Autodesk Fusion 360 part; units mm, degrees
(part 3 of 7)
sketch "T nut envelope sketch (3)" plane through (0, 0, 17) normal (0, 0, 1) x (1, 0, 0) in component "REFERENCE M5 slot-6 T nut 02"
  line L0 (7.2, 223) -> (16.8, 223)
  line L1 (16.8, 223) -> (16.8, 233)
  line L2 (16.8, 233) -> (7.2, 233)
  line L3 (7.2, 233) -> (7.2, 223)
  dimension "d912" = 7.2
  dimension "d913" = 223
  dimension "d914" = 9.6
  dimension "d915" = 10
  constraint horizontal L0
  constraint vertical L1
  constraint horizontal L2
  constraint vertical L3
  measures "d912" horizontal distance of origin L0.start
  measures "d913" vertical distance of origin L0.start
  measures "d914" horizontal distance of L0.start L0.end
  measures "d915" vertical distance of L0.end L1.end
extrude "T nut envelope''" add sketch "T nut envelope sketch (3)" along normal blind 4 separate body makes body 30 in component "REFERENCE M5 slot-6 T nut 02"
ref_plane "WorkPlane2" through (0, 0, 17) normal (0, 0, 1) x (1, 0, 0) in component "REFERENCE M5 slot-6 T nut 02"
sketch "Thread envelope sketch (3)" plane through (0, 0, 17) normal (0, 0, 1) x (1, 0, 0) in component "REFERENCE M5 slot-6 T nut 02"
  circle A0 centre (12, 228) radius 2.6
  dimension "d920" = 12
  dimension "d921" = 228
  dimension "d922" = 5.2
  measures "d920" horizontal distance of origin A0.centre
  measures "d921" vertical distance of origin A0.centre
  measures "d922" diameter of A0
extrude "Thread envelope''" cut sketch "Thread envelope sketch (3)" along normal blind 4 bodies 29 in component "REFERENCE M5 screw 02 - length follows stack"
extrude "Extrude2''" cut sketch "Thread envelope sketch (3)" along normal blind 4 bodies 30 in component "REFERENCE M5 slot-6 T nut 02"
ref_plane "WorkPlane1" through (0, 0, -2) normal (0, 0, 1) x (1, 0, 0) in component "METAL cap 10"
sketch "Visible cap sketch (4)" plane through (0, 0, -2) normal (0, 0, 1) x (1, 0, 0) in component "METAL cap 10"
  circle A0 centre (120, 12) radius 9
  dimension "d929" = 120
  dimension "d930" = 12
  dimension "d931" = 18
  measures "d929" horizontal distance of origin A0.centre
  measures "d930" vertical distance of origin A0.centre
  measures "d931" diameter of A0
extrude "Visible cap'''" add sketch "Visible cap sketch (4)" along normal blind 2 separate body makes body 31 in component "METAL cap 10"
ref_plane "WorkPlane2" through (0, 0, -2) normal (0, 0, 1) x (1, 0, 0) in component "METAL cap 10"
sketch "M5 clearance sketch (4)" plane through (0, 0, -2) normal (0, 0, 1) x (1, 0, 0) in component "METAL cap 10"
  circle A0 centre (120, 12) radius 2.75
  dimension "d936" = 120
  dimension "d937" = 12
  dimension "d938" = 5.5
  measures "d936" horizontal distance of origin A0.centre
  measures "d937" vertical distance of origin A0.centre
  measures "d938" diameter of A0
extrude "M5 clearance'''" cut sketch "M5 clearance sketch (4)" along normal blind 2 bodies 31 in component "METAL cap 10"
ref_plane "WorkPlane1" through (0, 0, 5) normal (0, 0, 1) x (1, 0, 0) in component "PRINT rear bearing seat 10"
sketch "Rear bearing seat sketch (4)" plane through (0, 0, 5) normal (0, 0, 1) x (1, 0, 0) in component "PRINT rear bearing seat 10"
  circle A0 centre (120, 12) radius 9
  dimension "d943" = 120
  dimension "d944" = 12
  dimension "d945" = 18
  measures "d943" horizontal distance of origin A0.centre
  measures "d944" vertical distance of origin A0.centre
  measures "d945" diameter of A0
extrude "Rear bearing seat'''" add sketch "Rear bearing seat sketch (4)" along normal blind 2 separate body makes body 32 in component "PRINT rear bearing seat 10"
ref_plane "WorkPlane2" through (0, 0, 5) normal (0, 0, 1) x (1, 0, 0) in component "PRINT rear bearing seat 10"
sketch "Shoulder clearance sketch (4)" plane through (0, 0, 5) normal (0, 0, 1) x (1, 0, 0) in component "PRINT rear bearing seat 10"
  circle A0 centre (120, 12) radius 4.2
  dimension "d950" = 120
  dimension "d951" = 12
  dimension "d952" = 8.4
  measures "d950" horizontal distance of origin A0.centre
  measures "d951" vertical distance of origin A0.centre
  measures "d952" diameter of A0
extrude "Shoulder clearance'''" cut sketch "Shoulder clearance sketch (4)" along normal blind 2 bodies 32 in component "PRINT rear bearing seat 10"
sketch "8 mm shoulder sketch (4)" plane through (0, 0, 0) normal (0, 0, 1) x (1, 0, 0) in component "METAL stepped compression spacer 10"
  circle A0 centre (120, 12) radius 4
  dimension "d955" = 120
  dimension "d956" = 12
  dimension "d957" = 8
  measures "d955" horizontal distance of origin A0.centre
  measures "d956" vertical distance of origin A0.centre
  measures "d957" diameter of A0
extrude "8 mm shoulder'''" add sketch "8 mm shoulder sketch (4)" along normal blind 7 separate body makes body 33 in component "METAL stepped compression spacer 10"
ref_plane "WorkPlane1" through (0, 0, 7) normal (0, 0, 1) x (1, 0, 0) in component "METAL stepped compression spacer 10"
sketch "12 mm base sketch (4)" plane through (0, 0, 7) normal (0, 0, 1) x (1, 0, 0) in component "METAL stepped compression spacer 10"
  circle A0 centre (120, 12) radius 6
  dimension "d962" = 120
  dimension "d963" = 12
  dimension "d964" = 12
  measures "d962" horizontal distance of origin A0.centre
  measures "d963" vertical distance of origin A0.centre
  measures "d964" diameter of A0
extrude "12 mm base'''" add sketch "12 mm base sketch (4)" along normal blind 8 bodies 33 in component "METAL stepped compression spacer 10"
sketch "Through bore sketch (4)" plane through (0, 0, 0) normal (0, 0, 1) x (1, 0, 0) in component "METAL stepped compression spacer 10"
  circle A0 centre (120, 12) radius 2.75
  dimension "d967" = 120
  dimension "d968" = 12
  dimension "d969" = 5.5
  measures "d967" horizontal distance of origin A0.centre
  measures "d968" vertical distance of origin A0.centre
  measures "d969" diameter of A0
extrude "Through bore'''" cut sketch "Through bore sketch (4)" along normal blind 15 bodies 33 in component "METAL stepped compression spacer 10"
ref_plane "WorkPlane1" through (0, 0, -5) normal (0, 0, 1) x (1, 0, 0) in component "REFERENCE M5 screw 10 - length follows stack"
sketch "Nominal button head sketch (4)" plane through (0, 0, -5) normal (0, 0, 1) x (1, 0, 0) in component "REFERENCE M5 screw 10 - length follows stack"
  circle A0 centre (120, 12) radius 4.75
  dimension "d974" = 120
  dimension "d975" = 12
  dimension "d976" = 9.5
  measures "d974" horizontal distance of origin A0.centre
  measures "d975" vertical distance of origin A0.centre
  measures "d976" diameter of A0
extrude "Nominal button head'''" add sketch "Nominal button head sketch (4)" along normal blind 3 separate body makes body 34 in component "REFERENCE M5 screw 10 - length follows stack"
ref_plane "WorkPlane2" through (0, 0, -2) normal (0, 0, 1) x (1, 0, 0) in component "REFERENCE M5 screw 10 - length follows stack"
sketch "Unthreaded shank envelope sketch (4)" plane through (0, 0, -2) normal (0, 0, 1) x (1, 0, 0) in component "REFERENCE M5 screw 10 - length follows stack"
  circle A0 centre (120, 12) radius 2.5
  dimension "d981" = 120
  dimension "d982" = 12
  dimension "d983" = 5
  measures "d981" horizontal distance of origin A0.centre
  measures "d982" vertical distance of origin A0.centre
  measures "d983" diameter of A0
extrude "Unthreaded shank envelope'''" add sketch "Unthreaded shank envelope sketch (4)" along normal blind 22 bodies 34 in component "REFERENCE M5 screw 10 - length follows stack"
ref_plane "WorkPlane1" through (0, 0, 17) normal (0, 0, 1) x (1, 0, 0) in component "REFERENCE M5 slot-6 T nut 10"
sketch "T nut envelope sketch (4)" plane through (0, 0, 17) normal (0, 0, 1) x (1, 0, 0) in component "REFERENCE M5 slot-6 T nut 10"
  line L0 (115.2, 7) -> (124.8, 7)
  line L1 (124.8, 7) -> (124.8, 17)
  line L2 (124.8, 17) -> (115.2, 17)
  line L3 (115.2, 17) -> (115.2, 7)
  dimension "d988" = 115.2
  dimension "d989" = 7
  dimension "d990" = 9.6
  dimension "d991" = 10
  constraint horizontal L0
  constraint vertical L1
  constraint horizontal L2
  constraint vertical L3
  measures "d988" horizontal distance of origin L0.start
  measures "d989" vertical distance of origin L0.start
  measures "d990" horizontal distance of L0.start L0.end
  measures "d991" vertical distance of L0.end L1.end
extrude "T nut envelope'''" add sketch "T nut envelope sketch (4)" along normal blind 4 separate body makes body 35 in component "REFERENCE M5 slot-6 T nut 10"
ref_plane "WorkPlane2" through (0, 0, 17) normal (0, 0, 1) x (1, 0, 0) in component "REFERENCE M5 slot-6 T nut 10"
sketch "Thread envelope sketch (4)" plane through (0, 0, 17) normal (0, 0, 1) x (1, 0, 0) in component "REFERENCE M5 slot-6 T nut 10"
  circle A0 centre (120, 12) radius 2.6
  dimension "d996" = 120
  dimension "d997" = 12
  dimension "d998" = 5.2
  measures "d996" horizontal distance of origin A0.centre
  measures "d997" vertical distance of origin A0.centre
  measures "d998" diameter of A0
extrude "Thread envelope'''" cut sketch "Thread envelope sketch (4)" along normal blind 4 bodies 34 in component "REFERENCE M5 screw 10 - length follows stack"
extrude "Extrude2'''" cut sketch "Thread envelope sketch (4)" along normal blind 4 bodies 35 in component "REFERENCE M5 slot-6 T nut 10"
ref_plane "WorkPlane1" through (0, 0, -2) normal (0, 0, 1) x (1, 0, 0) in component "METAL cap 11"
sketch "Visible cap sketch (5)" plane through (0, 0, -2) normal (0, 0, 1) x (1, 0, 0) in component "METAL cap 11"
  circle A0 centre (120, 120) radius 9
  dimension "d1005" = 120
  dimension "d1006" = 120
  dimension "d1007" = 18
  measures "d1005" horizontal distance of origin A0.centre
  measures "d1006" vertical distance of origin A0.centre
  measures "d1007" diameter of A0
extrude "Visible cap''''" add sketch "Visible cap sketch (5)" along normal blind 2 separate body makes body 36 in component "METAL cap 11"
ref_plane "WorkPlane2" through (0, 0, -2) normal (0, 0, 1) x (1, 0, 0) in component "METAL cap 11"
sketch "M5 clearance sketch (5)" plane through (0, 0, -2) normal (0, 0, 1) x (1, 0, 0) in component "METAL cap 11"
  circle A0 centre (120, 120) radius 2.75
  dimension "d1012" = 120
  dimension "d1013" = 120
  dimension "d1014" = 5.5
  measures "d1012" horizontal distance of origin A0.centre
  measures "d1013" vertical distance of origin A0.centre
  measures "d1014" diameter of A0
extrude "M5 clearance''''" cut sketch "M5 clearance sketch (5)" along normal blind 2 bodies 36 in component "METAL cap 11"
ref_plane "WorkPlane1" through (0, 0, 5) normal (0, 0, 1) x (1, 0, 0) in component "PRINT rear bearing seat 11"
sketch "Rear bearing seat sketch (5)" plane through (0, 0, 5) normal (0, 0, 1) x (1, 0, 0) in component "PRINT rear bearing seat 11"
  circle A0 centre (120, 120) radius 9
  dimension "d1019" = 120
  dimension "d1020" = 120
  dimension "d1021" = 18
  measures "d1019" horizontal distance of origin A0.centre
  measures "d1020" vertical distance of origin A0.centre
  measures "d1021" diameter of A0
extrude "Rear bearing seat''''" add sketch "Rear bearing seat sketch (5)" along normal blind 2 separate body makes body 37 in component "PRINT rear bearing seat 11"
ref_plane "WorkPlane2" through (0, 0, 5) normal (0, 0, 1) x (1, 0, 0) in component "PRINT rear bearing seat 11"
sketch "Shoulder clearance sketch (5)" plane through (0, 0, 5) normal (0, 0, 1) x (1, 0, 0) in component "PRINT rear bearing seat 11"
  circle A0 centre (120, 120) radius 4.2
  dimension "d1026" = 120
  dimension "d1027" = 120
  dimension "d1028" = 8.4
  measures "d1026" horizontal distance of origin A0.centre
  measures "d1027" vertical distance of origin A0.centre
  measures "d1028" diameter of A0
extrude "Shoulder clearance''''" cut sketch "Shoulder clearance sketch (5)" along normal blind 2 bodies 37 in component "PRINT rear bearing seat 11"
sketch "8 mm shoulder sketch (5)" plane through (0, 0, 0) normal (0, 0, 1) x (1, 0, 0) in component "METAL stepped compression spacer 11"
  circle A0 centre (120, 120) radius 4
  dimension "d1031" = 120
  dimension "d1032" = 120
  dimension "d1033" = 8
  measures "d1031" horizontal distance of origin A0.centre
  measures "d1032" vertical distance of origin A0.centre
  measures "d1033" diameter of A0
extrude "8 mm shoulder''''" add sketch "8 mm shoulder sketch (5)" along normal blind 7 separate body makes body 38 in component "METAL stepped compression spacer 11"
ref_plane "WorkPlane1" through (0, 0, 7) normal (0, 0, 1) x (1, 0, 0) in component "METAL stepped compression spacer 11"
sketch "12 mm base sketch (5)" plane through (0, 0, 7) normal (0, 0, 1) x (1, 0, 0) in component "METAL stepped compression spacer 11"
  circle A0 centre (120, 120) radius 6
  dimension "d1038" = 120
  dimension "d1039" = 120
  dimension "d1040" = 12
  measures "d1038" horizontal distance of origin A0.centre
  measures "d1039" vertical distance of origin A0.centre
  measures "d1040" diameter of A0
extrude "12 mm base''''" add sketch "12 mm base sketch (5)" along normal blind 8 bodies 38 in component "METAL stepped compression spacer 11"
sketch "Through bore sketch (5)" plane through (0, 0, 0) normal (0, 0, 1) x (1, 0, 0) in component "METAL stepped compression spacer 11"
  circle A0 centre (120, 120) radius 2.75
  dimension "d1043" = 120
  dimension "d1044" = 120
  dimension "d1045" = 5.5
  measures "d1043" horizontal distance of origin A0.centre
  measures "d1044" vertical distance of origin A0.centre
  measures "d1045" diameter of A0
extrude "Through bore''''" cut sketch "Through bore sketch (5)" along normal blind 15 bodies 38 in component "METAL stepped compression spacer 11"
ref_plane "WorkPlane1" through (0, 0, -5) normal (0, 0, 1) x (1, 0, 0) in component "REFERENCE M5 screw 11 - length follows stack"
sketch "Nominal button head sketch (5)" plane through (0, 0, -5) normal (0, 0, 1) x (1, 0, 0) in component "REFERENCE M5 screw 11 - length follows stack"
  circle A0 centre (120, 120) radius 4.75
  dimension "d1050" = 120
  dimension "d1051" = 120
  dimension "d1052" = 9.5
  measures "d1050" horizontal distance of origin A0.centre
  measures "d1051" vertical distance of origin A0.centre
  measures "d1052" diameter of A0
extrude "Nominal button head''''" add sketch "Nominal button head sketch (5)" along normal blind 3 separate body makes body 39 in component "REFERENCE M5 screw 11 - length follows stack"
ref_plane "WorkPlane2" through (0, 0, -2) normal (0, 0, 1) x (1, 0, 0) in component "REFERENCE M5 screw 11 - length follows stack"
sketch "Unthreaded shank envelope sketch (5)" plane through (0, 0, -2) normal (0, 0, 1) x (1, 0, 0) in component "REFERENCE M5 screw 11 - length follows stack"
  circle A0 centre (120, 120) radius 2.5
  dimension "d1057" = 120
  dimension "d1058" = 120
  dimension "d1059" = 5
  measures "d1057" horizontal distance of origin A0.centre
  measures "d1058" vertical distance of origin A0.centre
  measures "d1059" diameter of A0
extrude "Unthreaded shank envelope''''" add sketch "Unthreaded shank envelope sketch (5)" along normal blind 22 bodies 39 in component "REFERENCE M5 screw 11 - length follows stack"
ref_plane "WorkPlane1" through (0, 0, 17) normal (0, 0, 1) x (1, 0, 0) in component "REFERENCE M5 slot-6 T nut 11"
sketch "T nut envelope sketch (5)" plane through (0, 0, 17) normal (0, 0, 1) x (1, 0, 0) in component "REFERENCE M5 slot-6 T nut 11"
  line L0 (115.2, 115) -> (124.8, 115)
  line L1 (124.8, 115) -> (124.8, 125)
  line L2 (124.8, 125) -> (115.2, 125)
  line L3 (115.2, 125) -> (115.2, 115)
  dimension "d1064" = 115.2
  dimension "d1065" = 115
  dimension "d1066" = 9.6
  dimension "d1067" = 10
  constraint horizontal L0
  constraint vertical L1
  constraint horizontal L2
  constraint vertical L3
  measures "d1064" horizontal distance of origin L0.start
  measures "d1065" vertical distance of origin L0.start
  measures "d1066" horizontal distance of L0.start L0.end
  measures "d1067" vertical distance of L0.end L1.end
extrude "T nut envelope''''" add sketch "T nut envelope sketch (5)" along normal blind 4 separate body makes body 40 in component "REFERENCE M5 slot-6 T nut 11"
ref_plane "WorkPlane2" through (0, 0, 17) normal (0, 0, 1) x (1, 0, 0) in component "REFERENCE M5 slot-6 T nut 11"
sketch "Thread envelope sketch (5)" plane through (0, 0, 17) normal (0, 0, 1) x (1, 0, 0) in component "REFERENCE M5 slot-6 T nut 11"
  circle A0 centre (120, 120) radius 2.6
  dimension "d1072" = 120
  dimension "d1073" = 120
  dimension "d1074" = 5.2
  measures "d1072" horizontal distance of origin A0.centre
  measures "d1073" vertical distance of origin A0.centre
  measures "d1074" diameter of A0
extrude "Thread envelope''''" cut sketch "Thread envelope sketch (5)" along normal blind 4 bodies 39 in component "REFERENCE M5 screw 11 - length follows stack"
extrude "Extrude2''''" cut sketch "Thread envelope sketch (5)" along normal blind 4 bodies 40 in component "REFERENCE M5 slot-6 T nut 11"
ref_plane "WorkPlane1" through (0, 0, -2) normal (0, 0, 1) x (1, 0, 0) in component "METAL cap 12"
sketch "Visible cap sketch (6)" plane through (0, 0, -2) normal (0, 0, 1) x (1, 0, 0) in component "METAL cap 12"
  circle A0 centre (120, 228) radius 9
  dimension "d1081" = 120
  dimension "d1082" = 228
  dimension "d1083" = 18
  measures "d1081" horizontal distance of origin A0.centre
  measures "d1082" vertical distance of origin A0.centre
  measures "d1083" diameter of A0
extrude "Visible cap'''''" add sketch "Visible cap sketch (6)" along normal blind 2 separate body makes body 41 in component "METAL cap 12"
ref_plane "WorkPlane2" through (0, 0, -2) normal (0, 0, 1) x (1, 0, 0) in component "METAL cap 12"
sketch "M5 clearance sketch (6)" plane through (0, 0, -2) normal (0, 0, 1) x (1, 0, 0) in component "METAL cap 12"
  circle A0 centre (120, 228) radius 2.75
  dimension "d1088" = 120
  dimension "d1089" = 228
  dimension "d1090" = 5.5
  measures "d1088" horizontal distance of origin A0.centre
  measures "d1089" vertical distance of origin A0.centre
  measures "d1090" diameter of A0
extrude "M5 clearance'''''" cut sketch "M5 clearance sketch (6)" along normal blind 2 bodies 41 in component "METAL cap 12"
ref_plane "WorkPlane1" through (0, 0, 5) normal (0, 0, 1) x (1, 0, 0) in component "PRINT rear bearing seat 12"
sketch "Rear bearing seat sketch (6)" plane through (0, 0, 5) normal (0, 0, 1) x (1, 0, 0) in component "PRINT rear bearing seat 12"
  circle A0 centre (120, 228) radius 9
  dimension "d1095" = 120
  dimension "d1096" = 228
  dimension "d1097" = 18
  measures "d1095" horizontal distance of origin A0.centre
  measures "d1096" vertical distance of origin A0.centre
  measures "d1097" diameter of A0
extrude "Rear bearing seat'''''" add sketch "Rear bearing seat sketch (6)" along normal blind 2 separate body makes body 42 in component "PRINT rear bearing seat 12"
ref_plane "WorkPlane2" through (0, 0, 5) normal (0, 0, 1) x (1, 0, 0) in component "PRINT rear bearing seat 12"
sketch "Shoulder clearance sketch (6)" plane through (0, 0, 5) normal (0, 0, 1) x (1, 0, 0) in component "PRINT rear bearing seat 12"
  circle A0 centre (120, 228) radius 4.2
  dimension "d1102" = 120
  dimension "d1103" = 228
  dimension "d1104" = 8.4
  measures "d1102" horizontal distance of origin A0.centre
  measures "d1103" vertical distance of origin A0.centre
  measures "d1104" diameter of A0
extrude "Shoulder clearance'''''" cut sketch "Shoulder clearance sketch (6)" along normal blind 2 bodies 42 in component "PRINT rear bearing seat 12"
sketch "8 mm shoulder sketch (6)" plane through (0, 0, 0) normal (0, 0, 1) x (1, 0, 0) in component "METAL stepped compression spacer 12"
  circle A0 centre (120, 228) radius 4
  dimension "d1107" = 120
  dimension "d1108" = 228
  dimension "d1109" = 8
  measures "d1107" horizontal distance of origin A0.centre
  measures "d1108" vertical distance of origin A0.centre
  measures "d1109" diameter of A0
extrude "8 mm shoulder'''''" add sketch "8 mm shoulder sketch (6)" along normal blind 7 separate body makes body 43 in component "METAL stepped compression spacer 12"
ref_plane "WorkPlane1" through (0, 0, 7) normal (0, 0, 1) x (1, 0, 0) in component "METAL stepped compression spacer 12"
sketch "12 mm base sketch (6)" plane through (0, 0, 7) normal (0, 0, 1) x (1, 0, 0) in component "METAL stepped compression spacer 12"
  circle A0 centre (120, 228) radius 6
  dimension "d1114" = 120
  dimension "d1115" = 228
  dimension "d1116" = 12
  measures "d1114" horizontal distance of origin A0.centre
  measures "d1115" vertical distance of origin A0.centre
  measures "d1116" diameter of A0
extrude "12 mm base'''''" add sketch "12 mm base sketch (6)" along normal blind 8 bodies 43 in component "METAL stepped compression spacer 12"
sketch "Through bore sketch (6)" plane through (0, 0, 0) normal (0, 0, 1) x (1, 0, 0) in component "METAL stepped compression spacer 12"
  circle A0 centre (120, 228) radius 2.75
  dimension "d1119" = 120
  dimension "d1120" = 228
  dimension "d1121" = 5.5
  measures "d1119" horizontal distance of origin A0.centre
  measures "d1120" vertical distance of origin A0.centre
  measures "d1121" diameter of A0
extrude "Through bore'''''" cut sketch "Through bore sketch (6)" along normal blind 15 bodies 43 in component "METAL stepped compression spacer 12"
ref_plane "WorkPlane1" through (0, 0, -5) normal (0, 0, 1) x (1, 0, 0) in component "REFERENCE M5 screw 12 - length follows stack"
sketch "Nominal button head sketch (6)" plane through (0, 0, -5) normal (0, 0, 1) x (1, 0, 0) in component "REFERENCE M5 screw 12 - length follows stack"
  circle A0 centre (120, 228) radius 4.75
  dimension "d1126" = 120
  dimension "d1127" = 228
  dimension "d1128" = 9.5
  measures "d1126" horizontal distance of origin A0.centre
  measures "d1127" vertical distance of origin A0.centre
  measures "d1128" diameter of A0
extrude "Nominal button head'''''" add sketch "Nominal button head sketch (6)" along normal blind 3 separate body makes body 44 in component "REFERENCE M5 screw 12 - length follows stack"
ref_plane "WorkPlane2" through (0, 0, -2) normal (0, 0, 1) x (1, 0, 0) in component "REFERENCE M5 screw 12 - length follows stack"
sketch "Unthreaded shank envelope sketch (6)" plane through (0, 0, -2) normal (0, 0, 1) x (1, 0, 0) in component "REFERENCE M5 screw 12 - length follows stack"
  circle A0 centre (120, 228) radius 2.5
  dimension "d1133" = 120
  dimension "d1134" = 228
  dimension "d1135" = 5
  measures "d1133" horizontal distance of origin A0.centre
  measures "d1134" vertical distance of origin A0.centre
  measures "d1135" diameter of A0
extrude "Unthreaded shank envelope'''''" add sketch "Unthreaded shank envelope sketch (6)" along normal blind 22 bodies 44 in component "REFERENCE M5 screw 12 - length follows stack"
ref_plane "WorkPlane1" through (0, 0, 17) normal (0, 0, 1) x (1, 0, 0) in component "REFERENCE M5 slot-6 T nut 12"
sketch "T nut envelope sketch (6)" plane through (0, 0, 17) normal (0, 0, 1) x (1, 0, 0) in component "REFERENCE M5 slot-6 T nut 12"
  line L0 (115.2, 223) -> (124.8, 223)
  line L1 (124.8, 223) -> (124.8, 233)
  line L2 (124.8, 233) -> (115.2, 233)
  line L3 (115.2, 233) -> (115.2, 223)
  dimension "d1140" = 115.2
  dimension "d1141" = 223
  dimension "d1142" = 9.6
  dimension "d1143" = 10
  constraint horizontal L0
  constraint vertical L1
  constraint horizontal L2
  constraint vertical L3
  measures "d1140" horizontal distance of origin L0.start
  measures "d1141" vertical distance of origin L0.start
  measures "d1142" horizontal distance of L0.start L0.end
  measures "d1143" vertical distance of L0.end L1.end
extrude "T nut envelope'''''" add sketch "T nut envelope sketch (6)" along normal blind 4 separate body makes body 45 in component "REFERENCE M5 slot-6 T nut 12"
ref_plane "WorkPlane2" through (0, 0, 17) normal (0, 0, 1) x (1, 0, 0) in component "REFERENCE M5 slot-6 T nut 12"
sketch "Thread envelope sketch (6)" plane through (0, 0, 17) normal (0, 0, 1) x (1, 0, 0) in component "REFERENCE M5 slot-6 T nut 12"
  circle A0 centre (120, 228) radius 2.6
  dimension "d1148" = 120
  dimension "d1149" = 228
  dimension "d1150" = 5.2
  measures "d1148" horizontal distance of origin A0.centre
  measures "d1149" vertical distance of origin A0.centre
  measures "d1150" diameter of A0
extrude "Thread envelope'''''" cut sketch "Thread envelope sketch (6)" along normal blind 4 bodies 44 in component "REFERENCE M5 screw 12 - length follows stack"
extrude "Extrude2'''''" cut sketch "Thread envelope sketch (6)" along normal blind 4 bodies 45 in component "REFERENCE M5 slot-6 T nut 12"
ref_plane "WorkPlane1" through (0, 0, -2) normal (0, 0, 1) x (1, 0, 0) in component "METAL cap 20"
sketch "Visible cap sketch (7)" plane through (0, 0, -2) normal (0, 0, 1) x (1, 0, 0) in component "METAL cap 20"
  circle A0 centre (228, 12) radius 9
  dimension "d1157" = 228
  dimension "d1158" = 12
  dimension "d1159" = 18
  measures "d1157" horizontal distance of origin A0.centre
  measures "d1158" vertical distance of origin A0.centre
  measures "d1159" diameter of A0
extrude "Visible cap''''''" add sketch "Visible cap sketch (7)" along normal blind 2 separate body makes body 46 in component "METAL cap 20"
ref_plane "WorkPlane2" through (0, 0, -2) normal (0, 0, 1) x (1, 0, 0) in component "METAL cap 20"
sketch "M5 clearance sketch (7)" plane through (0, 0, -2) normal (0, 0, 1) x (1, 0, 0) in component "METAL cap 20"
  circle A0 centre (228, 12) radius 2.75
  dimension "d1164" = 228
  dimension "d1165" = 12
  dimension "d1166" = 5.5
  measures "d1164" horizontal distance of origin A0.centre
  measures "d1165" vertical distance of origin A0.centre
  measures "d1166" diameter of A0
extrude "M5 clearance''''''" cut sketch "M5 clearance sketch (7)" along normal blind 2 bodies 46 in component "METAL cap 20"
ref_plane "WorkPlane1" through (0, 0, 5) normal (0, 0, 1) x (1, 0, 0) in component "PRINT rear bearing seat 20"
sketch "Rear bearing seat sketch (7)" plane through (0, 0, 5) normal (0, 0, 1) x (1, 0, 0) in component "PRINT rear bearing seat 20"
  circle A0 centre (228, 12) radius 9
  dimension "d1171" = 228
  dimension "d1172" = 12
  dimension "d1173" = 18
  measures "d1171" horizontal distance of origin A0.centre
  measures "d1172" vertical distance of origin A0.centre
  measures "d1173" diameter of A0
extrude "Rear bearing seat''''''" add sketch "Rear bearing seat sketch (7)" along normal blind 2 separate body makes body 47 in component "PRINT rear bearing seat 20"
ref_plane "WorkPlane2" through (0, 0, 5) normal (0, 0, 1) x (1, 0, 0) in component "PRINT rear bearing seat 20"
sketch "Shoulder clearance sketch (7)" plane through (0, 0, 5) normal (0, 0, 1) x (1, 0, 0) in component "PRINT rear bearing seat 20"
  circle A0 centre (228, 12) radius 4.2
  dimension "d1178" = 228
  dimension "d1179" = 12
  dimension "d1180" = 8.4
  measures "d1178" horizontal distance of origin A0.centre
  measures "d1179" vertical distance of origin A0.centre
  measures "d1180" diameter of A0
extrude "Shoulder clearance''''''" cut sketch "Shoulder clearance sketch (7)" along normal blind 2 bodies 47 in component "PRINT rear bearing seat 20"
sketch "8 mm shoulder sketch (7)" plane through (0, 0, 0) normal (0, 0, 1) x (1, 0, 0) in component "METAL stepped compression spacer 20"
  circle A0 centre (228, 12) radius 4
  dimension "d1183" = 228
  dimension "d1184" = 12
  dimension "d1185" = 8
  measures "d1183" horizontal distance of origin A0.centre
  measures "d1184" vertical distance of origin A0.centre
  measures "d1185" diameter of A0
extrude "8 mm shoulder''''''" add sketch "8 mm shoulder sketch (7)" along normal blind 7 separate body makes body 48 in component "METAL stepped compression spacer 20"
ref_plane "WorkPlane1" through (0, 0, 7) normal (0, 0, 1) x (1, 0, 0) in component "METAL stepped compression spacer 20"
sketch "12 mm base sketch (7)" plane through (0, 0, 7) normal (0, 0, 1) x (1, 0, 0) in component "METAL stepped compression spacer 20"
  circle A0 centre (228, 12) radius 6
  dimension "d1190" = 228
  dimension "d1191" = 12
  dimension "d1192" = 12
  measures "d1190" horizontal distance of origin A0.centre
  measures "d1191" vertical distance of origin A0.centre
  measures "d1192" diameter of A0
extrude "12 mm base''''''" add sketch "12 mm base sketch (7)" along normal blind 8 bodies 48 in component "METAL stepped compression spacer 20"
sketch "Through bore sketch (7)" plane through (0, 0, 0) normal (0, 0, 1) x (1, 0, 0) in component "METAL stepped compression spacer 20"
  circle A0 centre (228, 12) radius 2.75
  dimension "d1195" = 228
  dimension "d1196" = 12
  dimension "d1197" = 5.5
  measures "d1195" horizontal distance of origin A0.centre
  measures "d1196" vertical distance of origin A0.centre
  measures "d1197" diameter of A0
extrude "Through bore''''''" cut sketch "Through bore sketch (7)" along normal blind 15 bodies 48 in component "METAL stepped compression spacer 20"
ref_plane "WorkPlane1" through (0, 0, -5) normal (0, 0, 1) x (1, 0, 0) in component "REFERENCE M5 screw 20 - length follows stack"
sketch "Nominal button head sketch (7)" plane through (0, 0, -5) normal (0, 0, 1) x (1, 0, 0) in component "REFERENCE M5 screw 20 - length follows stack"
  circle A0 centre (228, 12) radius 4.75
  dimension "d1202" = 228
  dimension "d1203" = 12
  dimension "d1204" = 9.5
  measures "d1202" horizontal distance of origin A0.centre
  measures "d1203" vertical distance of origin A0.centre
  measures "d1204" diameter of A0
extrude "Nominal button head''''''" add sketch "Nominal button head sketch (7)" along normal blind 3 separate body makes body 49 in component "REFERENCE M5 screw 20 - length follows stack"
ref_plane "WorkPlane2" through (0, 0, -2) normal (0, 0, 1) x (1, 0, 0) in component "REFERENCE M5 screw 20 - length follows stack"
sketch "Unthreaded shank envelope sketch (7)" plane through (0, 0, -2) normal (0, 0, 1) x (1, 0, 0) in component "REFERENCE M5 screw 20 - length follows stack"
  circle A0 centre (228, 12) radius 2.5
  dimension "d1209" = 228
  dimension "d1210" = 12
  dimension "d1211" = 5
  measures "d1209" horizontal distance of origin A0.centre
  measures "d1210" vertical distance of origin A0.centre
  measures "d1211" diameter of A0
extrude "Unthreaded shank envelope''''''" add sketch "Unthreaded shank envelope sketch (7)" along normal blind 22 bodies 49 in component "REFERENCE M5 screw 20 - length follows stack"
ref_plane "WorkPlane1" through (0, 0, 17) normal (0, 0, 1) x (1, 0, 0) in component "REFERENCE M5 slot-6 T nut 20"
sketch "T nut envelope sketch (7)" plane through (0, 0, 17) normal (0, 0, 1) x (1, 0, 0) in component "REFERENCE M5 slot-6 T nut 20"
  line L0 (223.2, 7) -> (232.8, 7)
  line L1 (232.8, 7) -> (232.8, 17)
  line L2 (232.8, 17) -> (223.2, 17)
  line L3 (223.2, 17) -> (223.2, 7)
  dimension "d1216" = 223.2
  dimension "d1217" = 7
  dimension "d1218" = 9.6
  dimension "d1219" = 10
  constraint horizontal L0
  constraint vertical L1
  constraint horizontal L2
  constraint vertical L3
  measures "d1216" horizontal distance of origin L0.start
  measures "d1217" vertical distance of origin L0.start
  measures "d1218" horizontal distance of L0.start L0.end
  measures "d1219" vertical distance of L0.end L1.end
extrude "T nut envelope''''''" add sketch "T nut envelope sketch (7)" along normal blind 4 separate body makes body 50 in component "REFERENCE M5 slot-6 T nut 20"
ref_plane "WorkPlane2" through (0, 0, 17) normal (0, 0, 1) x (1, 0, 0) in component "REFERENCE M5 slot-6 T nut 20"
sketch "Thread envelope sketch (7)" plane through (0, 0, 17) normal (0, 0, 1) x (1, 0, 0) in component "REFERENCE M5 slot-6 T nut 20"
  circle A0 centre (228, 12) radius 2.6
  dimension "d1224" = 228
  dimension "d1225" = 12
  dimension "d1226" = 5.2
  measures "d1224" horizontal distance of origin A0.centre
  measures "d1225" vertical distance of origin A0.centre
  measures "d1226" diameter of A0
extrude "Thread envelope''''''" cut sketch "Thread envelope sketch (7)" along normal blind 4 bodies 49 in component "REFERENCE M5 screw 20 - length follows stack"
extrude "Extrude2''''''" cut sketch "Thread envelope sketch (7)" along normal blind 4 bodies 50 in component "REFERENCE M5 slot-6 T nut 20"
ref_plane "WorkPlane1" through (0, 0, -2) normal (0, 0, 1) x (1, 0, 0) in component "METAL cap 21"
sketch "Visible cap sketch (8)" plane through (0, 0, -2) normal (0, 0, 1) x (1, 0, 0) in component "METAL cap 21"
  circle A0 centre (228, 120) radius 9
  dimension "d1233" = 228
  dimension "d1234" = 120
  dimension "d1235" = 18
  measures "d1233" horizontal distance of origin A0.centre
  measures "d1234" vertical distance of origin A0.centre
  measures "d1235" diameter of A0
extrude "Visible cap'''''''" add sketch "Visible cap sketch (8)" along normal blind 2 separate body makes body 51 in component "METAL cap 21"
ref_plane "WorkPlane2" through (0, 0, -2) normal (0, 0, 1) x (1, 0, 0) in component "METAL cap 21"
sketch "M5 clearance sketch (8)" plane through (0, 0, -2) normal (0, 0, 1) x (1, 0, 0) in component "METAL cap 21"
  circle A0 centre (228, 120) radius 2.75
  dimension "d1240" = 228
  dimension "d1241" = 120
  dimension "d1242" = 5.5
  measures "d1240" horizontal distance of origin A0.centre
  measures "d1241" vertical distance of origin A0.centre
  measures "d1242" diameter of A0
extrude "M5 clearance'''''''" cut sketch "M5 clearance sketch (8)" along normal blind 2 bodies 51 in component "METAL cap 21"
ref_plane "WorkPlane1" through (0, 0, 5) normal (0, 0, 1) x (1, 0, 0) in component "PRINT rear bearing seat 21"
sketch "Rear bearing seat sketch (8)" plane through (0, 0, 5) normal (0, 0, 1) x (1, 0, 0) in component "PRINT rear bearing seat 21"
  circle A0 centre (228, 120) radius 9
  dimension "d1247" = 228
  dimension "d1248" = 120
  dimension "d1249" = 18
  measures "d1247" horizontal distance of origin A0.centre
  measures "d1248" vertical distance of origin A0.centre
  measures "d1249" diameter of A0
extrude "Rear bearing seat'''''''" add sketch "Rear bearing seat sketch (8)" along normal blind 2 separate body makes body 52 in component "PRINT rear bearing seat 21"
ref_plane "WorkPlane2" through (0, 0, 5) normal (0, 0, 1) x (1, 0, 0) in component "PRINT rear bearing seat 21"
sketch "Shoulder clearance sketch (8)" plane through (0, 0, 5) normal (0, 0, 1) x (1, 0, 0) in component "PRINT rear bearing seat 21"
  circle A0 centre (228, 120) radius 4.2
  dimension "d1254" = 228
  dimension "d1255" = 120
  dimension "d1256" = 8.4
  measures "d1254" horizontal distance of origin A0.centre
  measures "d1255" vertical distance of origin A0.centre
  measures "d1256" diameter of A0
extrude "Shoulder clearance'''''''" cut sketch "Shoulder clearance sketch (8)" along normal blind 2 bodies 52 in component "PRINT rear bearing seat 21"
sketch "8 mm shoulder sketch (8)" plane through (0, 0, 0) normal (0, 0, 1) x (1, 0, 0) in component "METAL stepped compression spacer 21"
  circle A0 centre (228, 120) radius 4
  dimension "d1259" = 228
  dimension "d1260" = 120
  dimension "d1261" = 8
  measures "d1259" horizontal distance of origin A0.centre
  measures "d1260" vertical distance of origin A0.centre
  measures "d1261" diameter of A0
extrude "8 mm shoulder'''''''" add sketch "8 mm shoulder sketch (8)" along normal blind 7 separate body makes body 53 in component "METAL stepped compression spacer 21"
ref_plane "WorkPlane1" through (0, 0, 7) normal (0, 0, 1) x (1, 0, 0) in component "METAL stepped compression spacer 21"
sketch "12 mm base sketch (8)" plane through (0, 0, 7) normal (0, 0, 1) x (1, 0, 0) in component "METAL stepped compression spacer 21"
  circle A0 centre (228, 120) radius 6
  dimension "d1266" = 228
  dimension "d1267" = 120
  dimension "d1268" = 12
  measures "d1266" horizontal distance of origin A0.centre
  measures "d1267" vertical distance of origin A0.centre
  measures "d1268" diameter of A0
extrude "12 mm base'''''''" add sketch "12 mm base sketch (8)" along normal blind 8 bodies 53 in component "METAL stepped compression spacer 21"
sketch "Through bore sketch (8)" plane through (0, 0, 0) normal (0, 0, 1) x (1, 0, 0) in component "METAL stepped compression spacer 21"
  circle A0 centre (228, 120) radius 2.75
  dimension "d1271" = 228
  dimension "d1272" = 120
  dimension "d1273" = 5.5
  measures "d1271" horizontal distance of origin A0.centre
  measures "d1272" vertical distance of origin A0.centre
  measures "d1273" diameter of A0
extrude "Through bore'''''''" cut sketch "Through bore sketch (8)" along normal blind 15 bodies 53 in component "METAL stepped compression spacer 21"
ref_plane "WorkPlane1" through (0, 0, -5) normal (0, 0, 1) x (1, 0, 0) in component "REFERENCE M5 screw 21 - length follows stack"
sketch "Nominal button head sketch (8)" plane through (0, 0, -5) normal (0, 0, 1) x (1, 0, 0) in component "REFERENCE M5 screw 21 - length follows stack"
  circle A0 centre (228, 120) radius 4.75
  dimension "d1278" = 228
  dimension "d1279" = 120
  dimension "d1280" = 9.5
  measures "d1278" horizontal distance of origin A0.centre
  measures "d1279" vertical distance of origin A0.centre
  measures "d1280" diameter of A0
extrude "Nominal button head'''''''" add sketch "Nominal button head sketch (8)" along normal blind 3 separate body makes body 54 in component "REFERENCE M5 screw 21 - length follows stack"
ref_plane "WorkPlane2" through (0, 0, -2) normal (0, 0, 1) x (1, 0, 0) in component "REFERENCE M5 screw 21 - length follows stack"
sketch "Unthreaded shank envelope sketch (8)" plane through (0, 0, -2) normal (0, 0, 1) x (1, 0, 0) in component "REFERENCE M5 screw 21 - length follows stack"
  circle A0 centre (228, 120) radius 2.5
  dimension "d1285" = 228
  dimension "d1286" = 120
  dimension "d1287" = 5
  measures "d1285" horizontal distance of origin A0.centre
  measures "d1286" vertical distance of origin A0.centre
  measures "d1287" diameter of A0
extrude "Unthreaded shank envelope'''''''" add sketch "Unthreaded shank envelope sketch (8)" along normal blind 22 bodies 54 in component "REFERENCE M5 screw 21 - length follows stack"
ref_plane "WorkPlane1" through (0, 0, 17) normal (0, 0, 1) x (1, 0, 0) in component "REFERENCE M5 slot-6 T nut 21"
sketch "T nut envelope sketch (8)" plane through (0, 0, 17) normal (0, 0, 1) x (1, 0, 0) in component "REFERENCE M5 slot-6 T nut 21"
  line L0 (223.2, 115) -> (232.8, 115)
  line L1 (232.8, 115) -> (232.8, 125)
  line L2 (232.8, 125) -> (223.2, 125)
  line L3 (223.2, 125) -> (223.2, 115)
  dimension "d1292" = 223.2
  dimension "d1293" = 115
  dimension "d1294" = 9.6
  dimension "d1295" = 10
  constraint horizontal L0
  constraint vertical L1
  constraint horizontal L2
  constraint vertical L3
  measures "d1292" horizontal distance of origin L0.start
  measures "d1293" vertical distance of origin L0.start
  measures "d1294" horizontal distance of L0.start L0.end
  measures "d1295" vertical distance of L0.end L1.end
extrude "T nut envelope'''''''" add sketch "T nut envelope sketch (8)" along normal blind 4 separate body makes body 55 in component "REFERENCE M5 slot-6 T nut 21"
ref_plane "WorkPlane2" through (0, 0, 17) normal (0, 0, 1) x (1, 0, 0) in component "REFERENCE M5 slot-6 T nut 21"
sketch "Thread envelope sketch (8)" plane through (0, 0, 17) normal (0, 0, 1) x (1, 0, 0) in component "REFERENCE M5 slot-6 T nut 21"
  circle A0 centre (228, 120) radius 2.6
  dimension "d1300" = 228
  dimension "d1301" = 120
  dimension "d1302" = 5.2
  measures "d1300" horizontal distance of origin A0.centre
  measures "d1301" vertical distance of origin A0.centre
  measures "d1302" diameter of A0
extrude "Thread envelope'''''''" cut sketch "Thread envelope sketch (8)" along normal blind 4 bodies 54 in component "REFERENCE M5 screw 21 - length follows stack"
extrude "Extrude2'''''''" cut sketch "Thread envelope sketch (8)" along normal blind 4 bodies 55 in component "REFERENCE M5 slot-6 T nut 21"
ref_plane "WorkPlane1" through (0, 0, -2) normal (0, 0, 1) x (1, 0, 0) in component "METAL cap 22"
sketch "Visible cap sketch (9)" plane through (0, 0, -2) normal (0, 0, 1) x (1, 0, 0) in component "METAL cap 22"
  circle A0 centre (228, 228) radius 9
  dimension "d1309" = 228
  dimension "d1310" = 228
  dimension "d1311" = 18
  measures "d1309" horizontal distance of origin A0.centre
  measures "d1310" vertical distance of origin A0.centre
  measures "d1311" diameter of A0
extrude "Visible cap''''''''" add sketch "Visible cap sketch (9)" along normal blind 2 separate body makes body 56 in component "METAL cap 22"
ref_plane "WorkPlane2" through (0, 0, -2) normal (0, 0, 1) x (1, 0, 0) in component "METAL cap 22"
sketch "M5 clearance sketch (9)" plane through (0, 0, -2) normal (0, 0, 1) x (1, 0, 0) in component "METAL cap 22"
  circle A0 centre (228, 228) radius 2.75
  dimension "d1316" = 228
  dimension "d1317" = 228
  dimension "d1318" = 5.5
  measures "d1316" horizontal distance of origin A0.centre
  measures "d1317" vertical distance of origin A0.centre
  measures "d1318" diameter of A0
extrude "M5 clearance''''''''" cut sketch "M5 clearance sketch (9)" along normal blind 2 bodies 56 in component "METAL cap 22"
ref_plane "WorkPlane1" through (0, 0, 5) normal (0, 0, 1) x (1, 0, 0) in component "PRINT rear bearing seat 22"
sketch "Rear bearing seat sketch (9)" plane through (0, 0, 5) normal (0, 0, 1) x (1, 0, 0) in component "PRINT rear bearing seat 22"
  circle A0 centre (228, 228) radius 9
  dimension "d1323" = 228
  dimension "d1324" = 228
  dimension "d1325" = 18
  measures "d1323" horizontal distance of origin A0.centre
  measures "d1324" vertical distance of origin A0.centre
  measures "d1325" diameter of A0
extrude "Rear bearing seat''''''''" add sketch "Rear bearing seat sketch (9)" along normal blind 2 separate body makes body 57 in component "PRINT rear bearing seat 22"
ref_plane "WorkPlane2" through (0, 0, 5) normal (0, 0, 1) x (1, 0, 0) in component "PRINT rear bearing seat 22"
sketch "Shoulder clearance sketch (9)" plane through (0, 0, 5) normal (0, 0, 1) x (1, 0, 0) in component "PRINT rear bearing seat 22"
  circle A0 centre (228, 228) radius 4.2
  dimension "d1330" = 228
  dimension "d1331" = 228
  dimension "d1332" = 8.4
  measures "d1330" horizontal distance of origin A0.centre
  measures "d1331" vertical distance of origin A0.centre
  measures "d1332" diameter of A0
extrude "Shoulder clearance''''''''" cut sketch "Shoulder clearance sketch (9)" along normal blind 2 bodies 57 in component "PRINT rear bearing seat 22"
sketch "8 mm shoulder sketch (9)" plane through (0, 0, 0) normal (0, 0, 1) x (1, 0, 0) in component "METAL stepped compression spacer 22"
  circle A0 centre (228, 228) radius 4
  dimension "d1335" = 228
  dimension "d1336" = 228
  dimension "d1337" = 8
  measures "d1335" horizontal distance of origin A0.centre
  measures "d1336" vertical distance of origin A0.centre
  measures "d1337" diameter of A0
extrude "8 mm shoulder''''''''" add sketch "8 mm shoulder sketch (9)" along normal blind 7 separate body makes body 58 in component "METAL stepped compression spacer 22"
ref_plane "WorkPlane1" through (0, 0, 7) normal (0, 0, 1) x (1, 0, 0) in component "METAL stepped compression spacer 22"
sketch "12 mm base sketch (9)" plane through (0, 0, 7) normal (0, 0, 1) x (1, 0, 0) in component "METAL stepped compression spacer 22"
  circle A0 centre (228, 228) radius 6
  dimension "d1342" = 228
  dimension "d1343" = 228
  dimension "d1344" = 12
  measures "d1342" horizontal distance of origin A0.centre
  measures "d1343" vertical distance of origin A0.centre
  measures "d1344" diameter of A0
extrude "12 mm base''''''''" add sketch "12 mm base sketch (9)" along normal blind 8 bodies 58 in component "METAL stepped compression spacer 22"
sketch "Through bore sketch (9)" plane through (0, 0, 0) normal (0, 0, 1) x (1, 0, 0) in component "METAL stepped compression spacer 22"
  circle A0 centre (228, 228) radius 2.75
  dimension "d1347" = 228
  dimension "d1348" = 228
  dimension "d1349" = 5.5
  measures "d1347" horizontal distance of origin A0.centre
  measures "d1348" vertical distance of origin A0.centre
  measures "d1349" diameter of A0
extrude "Through bore''''''''" cut sketch "Through bore sketch (9)" along normal blind 15 bodies 58 in component "METAL stepped compression spacer 22"
ref_plane "WorkPlane1" through (0, 0, -5) normal (0, 0, 1) x (1, 0, 0) in component "REFERENCE M5 screw 22 - length follows stack"
sketch "Nominal button head sketch (9)" plane through (0, 0, -5) normal (0, 0, 1) x (1, 0, 0) in component "REFERENCE M5 screw 22 - length follows stack"
  circle A0 centre (228, 228) radius 4.75
  dimension "d1354" = 228
  dimension "d1355" = 228
  dimension "d1356" = 9.5
  measures "d1354" horizontal distance of origin A0.centre
  measures "d1355" vertical distance of origin A0.centre
  measures "d1356" diameter of A0
extrude "Nominal button head''''''''" add sketch "Nominal button head sketch (9)" along normal blind 3 separate body makes body 59 in component "REFERENCE M5 screw 22 - length follows stack"
ref_plane "WorkPlane2" through (0, 0, -2) normal (0, 0, 1) x (1, 0, 0) in component "REFERENCE M5 screw 22 - length follows stack"
sketch "Unthreaded shank envelope sketch (9)" plane through (0, 0, -2) normal (0, 0, 1) x (1, 0, 0) in component "REFERENCE M5 screw 22 - length follows stack"
  circle A0 centre (228, 228) radius 2.5
  dimension "d1361" = 228
  dimension "d1362" = 228
  dimension "d1363" = 5
  measures "d1361" horizontal distance of origin A0.centre
  measures "d1362" vertical distance of origin A0.centre
  measures "d1363" diameter of A0
extrude "Unthreaded shank envelope''''''''" add sketch "Unthreaded shank envelope sketch (9)" along normal blind 22 bodies 59 in component "REFERENCE M5 screw 22 - length follows stack"
ref_plane "WorkPlane1" through (0, 0, 17) normal (0, 0, 1) x (1, 0, 0) in component "REFERENCE M5 slot-6 T nut 22"
sketch "T nut envelope sketch (9)" plane through (0, 0, 17) normal (0, 0, 1) x (1, 0, 0) in component "REFERENCE M5 slot-6 T nut 22"
  line L0 (223.2, 223) -> (232.8, 223)
  line L1 (232.8, 223) -> (232.8, 233)
  line L2 (232.8, 233) -> (223.2, 233)
  line L3 (223.2, 233) -> (223.2, 223)
  dimension "d1368" = 223.2
  dimension "d1369" = 223
  dimension "d1370" = 9.6
  dimension "d1371" = 10
  constraint horizontal L0
  constraint vertical L1
  constraint horizontal L2
  constraint vertical L3
  measures "d1368" horizontal distance of origin L0.start
  measures "d1369" vertical distance of origin L0.start
  measures "d1370" horizontal distance of L0.start L0.end
  measures "d1371" vertical distance of L0.end L1.end
extrude "T nut envelope''''''''" add sketch "T nut envelope sketch (9)" along normal blind 4 separate body makes body 60 in component "REFERENCE M5 slot-6 T nut 22"
ref_plane "WorkPlane2" through (0, 0, 17) normal (0, 0, 1) x (1, 0, 0) in component "REFERENCE M5 slot-6 T nut 22"
sketch "Thread envelope sketch (9)" plane through (0, 0, 17) normal (0, 0, 1) x (1, 0, 0) in component "REFERENCE M5 slot-6 T nut 22"
  circle A0 centre (228, 228) radius 2.6
  dimension "d1376" = 228
  dimension "d1377" = 228
  dimension "d1378" = 5.2
  measures "d1376" horizontal distance of origin A0.centre
  measures "d1377" vertical distance of origin A0.centre
  measures "d1378" diameter of A0
extrude "Thread envelope''''''''" cut sketch "Thread envelope sketch (9)" along normal blind 4 bodies 59 in component "REFERENCE M5 screw 22 - length follows stack"
extrude "Extrude2''''''''" cut sketch "Thread envelope sketch (9)" along normal blind 4 bodies 60 in component "REFERENCE M5 slot-6 T nut 22"
ref_plane "WorkPlane4" through (0, 0, 35) normal (0, 0, 1) x (1, 0, 0) in component "Vertical rail 0 - nominal 2020 slot-6 envelope"
sketch "Rear slot mouth sketch" plane through (0, 0, 35) normal (0, 0, 1) x (1, 0, 0) in component "Vertical rail 0 - nominal 2020 slot-6 envelope"
  line L0 (9, 2) -> (15, 2)
  line L1 (15, 2) -> (15, 238)
  line L2 (15, 238) -> (9, 238)
  line L3 (9, 238) -> (9, 2)
  dimension "d1385" = 9
  dimension "d1386" = 2
  dimension "d1387" = 6
  dimension "d1388" = 236
  constraint horizontal L0
  constraint vertical L1
  constraint horizontal L2
  constraint vertical L3
  measures "d1385" horizontal distance of origin L0.start
  measures "d1386" vertical distance of origin L0.start
  measures "d1387" horizontal distance of L0.start L0.end
  measures "d1388" vertical distance of L0.end L1.end
extrude "Rear slot mouth" cut sketch "Rear slot mouth sketch" against normal blind 1.8 bodies 9 in component "Vertical rail 0 - nominal 2020 slot-6 envelope"
ref_plane "WorkPlane5" through (0, 0, 33.2) normal (0, 0, 1) x (1, 0, 0) in component "Vertical rail 0 - nominal 2020 slot-6 envelope"
sketch "Rear T nut cavity sketch" plane through (0, 0, 33.2) normal (0, 0, 1) x (1, 0, 0) in component "Vertical rail 0 - nominal 2020 slot-6 envelope"
  line L0 (7, 2) -> (17, 2)
  line L1 (17, 2) -> (17, 238)
  line L2 (17, 238) -> (7, 238)
  line L3 (7, 238) -> (7, 2)
  dimension "d1393" = 7
  dimension "d1394" = 2
  dimension "d1395" = 10
  dimension "d1396" = 236
  constraint horizontal L0
  constraint vertical L1
  constraint horizontal L2
  constraint vertical L3
  measures "d1393" horizontal distance of origin L0.start
  measures "d1394" vertical distance of origin L0.start
  measures "d1395" horizontal distance of L0.start L0.end
  measures "d1396" vertical distance of L0.end L1.end
extrude "Rear T nut cavity" cut sketch "Rear T nut cavity sketch" against normal blind 4.2 bodies 9 in component "Vertical rail 0 - nominal 2020 slot-6 envelope"
ref_plane "WorkPlane4" through (0, 0, 35) normal (0, 0, 1) x (1, 0, 0) in component "Vertical rail 1 - nominal 2020 slot-6 envelope"